Autodesk Fusion 360 part; units mm, degrees
(part 3 of 3)
sketch "M3 screw shaft (32, 16) layout" plane through (0, 0, 70.4) normal (0, 0, 1) x (1, 0, 0) in component "REFERENCE - six M3 x 10 button screws and washers"
  circle A0 centre (32, 16) radius 1.5
extrude "M3 screw shaft (32, 16)" add sketch "M3 screw shaft (32, 16) layout" along normal blind 10 bodies 31 in component "REFERENCE - six M3 x 10 button screws and washers"
ref_plane "WorkPlane6" through (0, 0, 79.9) normal (0, 0, 1) x (1, 0, 0) in component "REFERENCE - six M3 x 10 button screws and washers"
sketch "M3 washer OD (32, 16) layout" plane through (0, 0, 79.9) normal (0, 0, 1) x (1, 0, 0) in component "REFERENCE - six M3 x 10 button screws and washers"
  circle A0 centre (32, 16) radius 3.5
extrude "M3 washer OD (32, 16)" add sketch "M3 washer OD (32, 16) layout" along normal blind 0.5 bodies 31 in component "REFERENCE - six M3 x 10 button screws and washers"
ref_plane "WorkPlane3" through (0, 0, 71.1) normal (0, 0, 1) x (1, 0, 0) in component "REFERENCE - six M3 DIN 934 nuts"
sketch "M3 nut (32, 16) outline" plane through (0, 0, 71.1) normal (0, 0, 1) x (1, 0, 0) in component "REFERENCE - six M3 DIN 934 nuts"
  line L0 (35.1754, 16) -> (33.5877, 18.75)
  line L1 (33.5877, 18.75) -> (30.4123, 18.75)
  line L2 (30.4123, 18.75) -> (28.8246, 16)
  line L3 (28.8246, 16) -> (30.4123, 13.25)
  line L4 (30.4123, 13.25) -> (33.5877, 13.25)
  line L5 (33.5877, 13.25) -> (35.1754, 16)
extrude "M3 nut (32, 16)" add sketch "M3 nut (32, 16) outline" along normal blind 2.4 separate body makes body 32 in component "REFERENCE - six M3 DIN 934 nuts"
ref_plane "WorkPlane4" through (0, 0, 71) normal (0, 0, 1) x (1, 0, 0) in component "REFERENCE - six M3 DIN 934 nuts"
sketch "M3 thread clearance envelope (32, 16) layout" plane through (0, 0, 71) normal (0, 0, 1) x (1, 0, 0) in component "REFERENCE - six M3 DIN 934 nuts"
  circle A0 centre (32, 16) radius 1.6
extrude "M3 thread clearance envelope (32, 16)" cut sketch "M3 thread clearance envelope (32, 16) layout" along normal blind 2.6 bodies 30 32 in component "REFERENCE - six M3 DIN 934 nuts"
ref_plane "WorkPlane7" through (0, 0, 80.4) normal (0, 0, 1) x (1, 0, 0) in component "REFERENCE - six M3 x 10 button screws and washers"
sketch "M3 button head envelope (182, 16) layout" plane through (0, 0, 80.4) normal (0, 0, 1) x (1, 0, 0) in component "REFERENCE - six M3 x 10 button screws and washers"
  circle A0 centre (182, 16) radius 2.85
extrude "M3 button head envelope (182, 16)" add sketch "M3 button head envelope (182, 16) layout" along normal blind 1.65 separate body makes body 33 in component "REFERENCE - six M3 x 10 button screws and washers"
ref_plane "WorkPlane8" through (0, 0, 70.4) normal (0, 0, 1) x (1, 0, 0) in component "REFERENCE - six M3 x 10 button screws and washers"
sketch "M3 screw shaft (182, 16) layout" plane through (0, 0, 70.4) normal (0, 0, 1) x (1, 0, 0) in component "REFERENCE - six M3 x 10 button screws and washers"
  circle A0 centre (182, 16) radius 1.5
extrude "M3 screw shaft (182, 16)" add sketch "M3 screw shaft (182, 16) layout" along normal blind 10 bodies 33 in component "REFERENCE - six M3 x 10 button screws and washers"
ref_plane "WorkPlane9" through (0, 0, 79.9) normal (0, 0, 1) x (1, 0, 0) in component "REFERENCE - six M3 x 10 button screws and washers"
sketch "M3 washer OD (182, 16) layout" plane through (0, 0, 79.9) normal (0, 0, 1) x (1, 0, 0) in component "REFERENCE - six M3 x 10 button screws and washers"
  circle A0 centre (182, 16) radius 3.5
extrude "M3 washer OD (182, 16)" add sketch "M3 washer OD (182, 16) layout" along normal blind 0.5 bodies 33 in component "REFERENCE - six M3 x 10 button screws and washers"
ref_plane "WorkPlane5" through (0, 0, 71.1) normal (0, 0, 1) x (1, 0, 0) in component "REFERENCE - six M3 DIN 934 nuts"
sketch "M3 nut (182, 16) outline" plane through (0, 0, 71.1) normal (0, 0, 1) x (1, 0, 0) in component "REFERENCE - six M3 DIN 934 nuts"
  line L0 (185.1754, 16) -> (183.5877, 18.75)
  line L1 (183.5877, 18.75) -> (180.4123, 18.75)
  line L2 (180.4123, 18.75) -> (178.8246, 16)
  line L3 (178.8246, 16) -> (180.4123, 13.25)
  line L4 (180.4123, 13.25) -> (183.5877, 13.25)
  line L5 (183.5877, 13.25) -> (185.1754, 16)
extrude "M3 nut (182, 16)" add sketch "M3 nut (182, 16) outline" along normal blind 2.4 separate body makes body 34 in component "REFERENCE - six M3 DIN 934 nuts"
ref_plane "WorkPlane6" through (0, 0, 71) normal (0, 0, 1) x (1, 0, 0) in component "REFERENCE - six M3 DIN 934 nuts"
sketch "M3 thread clearance envelope (182, 16) layout" plane through (0, 0, 71) normal (0, 0, 1) x (1, 0, 0) in component "REFERENCE - six M3 DIN 934 nuts"
  circle A0 centre (182, 16) radius 1.6
extrude "M3 thread clearance envelope (182, 16)" cut sketch "M3 thread clearance envelope (182, 16) layout" along normal blind 2.6 bodies 30 32 34 in component "REFERENCE - six M3 DIN 934 nuts"
ref_plane "WorkPlane10" through (0, 0, 80.4) normal (0, 0, 1) x (1, 0, 0) in component "REFERENCE - six M3 x 10 button screws and washers"
sketch "M3 button head envelope (196, 16) layout" plane through (0, 0, 80.4) normal (0, 0, 1) x (1, 0, 0) in component "REFERENCE - six M3 x 10 button screws and washers"
  circle A0 centre (196, 16) radius 2.85
extrude "M3 button head envelope (196, 16)" add sketch "M3 button head envelope (196, 16) layout" along normal blind 1.65 separate body makes body 35 in component "REFERENCE - six M3 x 10 button screws and washers"
ref_plane "WorkPlane11" through (0, 0, 70.4) normal (0, 0, 1) x (1, 0, 0) in component "REFERENCE - six M3 x 10 button screws and washers"
sketch "M3 screw shaft (196, 16) layout" plane through (0, 0, 70.4) normal (0, 0, 1) x (1, 0, 0) in component "REFERENCE - six M3 x 10 button screws and washers"
  circle A0 centre (196, 16) radius 1.5
extrude "M3 screw shaft (196, 16)" add sketch "M3 screw shaft (196, 16) layout" along normal blind 10 bodies 35 in component "REFERENCE - six M3 x 10 button screws and washers"
ref_plane "WorkPlane12" through (0, 0, 79.9) normal (0, 0, 1) x (1, 0, 0) in component "REFERENCE - six M3 x 10 button screws and washers"
sketch "M3 washer OD (196, 16) layout" plane through (0, 0, 79.9) normal (0, 0, 1) x (1, 0, 0) in component "REFERENCE - six M3 x 10 button screws and washers"
  circle A0 centre (196, 16) radius 3.5
extrude "M3 washer OD (196, 16)" add sketch "M3 washer OD (196, 16) layout" along normal blind 0.5 bodies 35 in component "REFERENCE - six M3 x 10 button screws and washers"
ref_plane "WorkPlane7" through (0, 0, 71.1) normal (0, 0, 1) x (1, 0, 0) in component "REFERENCE - six M3 DIN 934 nuts"
sketch "M3 nut (196, 16) outline" plane through (0, 0, 71.1) normal (0, 0, 1) x (1, 0, 0) in component "REFERENCE - six M3 DIN 934 nuts"
  line L0 (199.1754, 16) -> (197.5877, 18.75)
  line L1 (197.5877, 18.75) -> (194.4123, 18.75)
  line L2 (194.4123, 18.75) -> (192.8246, 16)
  line L3 (192.8246, 16) -> (194.4123, 13.25)
  line L4 (194.4123, 13.25) -> (197.5877, 13.25)
  line L5 (197.5877, 13.25) -> (199.1754, 16)
extrude "M3 nut (196, 16)" add sketch "M3 nut (196, 16) outline" along normal blind 2.4 separate body makes body 36 in component "REFERENCE - six M3 DIN 934 nuts"
ref_plane "WorkPlane8" through (0, 0, 71) normal (0, 0, 1) x (1, 0, 0) in component "REFERENCE - six M3 DIN 934 nuts"
sketch "M3 thread clearance envelope (196, 16) layout" plane through (0, 0, 71) normal (0, 0, 1) x (1, 0, 0) in component "REFERENCE - six M3 DIN 934 nuts"
  circle A0 centre (196, 16) radius 1.6
extrude "M3 thread clearance envelope (196, 16)" cut sketch "M3 thread clearance envelope (196, 16) layout" along normal blind 2.6 bodies 30 32 34 36 in component "REFERENCE - six M3 DIN 934 nuts"
ref_plane "WorkPlane13" through (0, 0, 80.4) normal (0, 0, 1) x (1, 0, 0) in component "REFERENCE - six M3 x 10 button screws and washers"
sketch "M3 button head envelope (92, -2.5) layout" plane through (0, 0, 80.4) normal (0, 0, 1) x (1, 0, 0) in component "REFERENCE - six M3 x 10 button screws and washers"
  circle A0 centre (92, -2.5) radius 2.85
extrude "M3 button head envelope (92, -2.5)" add sketch "M3 button head envelope (92, -2.5) layout" along normal blind 1.65 separate body makes body 37 in component "REFERENCE - six M3 x 10 button screws and washers"
ref_plane "WorkPlane14" through (0, 0, 70.4) normal (0, 0, 1) x (1, 0, 0) in component "REFERENCE - six M3 x 10 button screws and washers"
sketch "M3 screw shaft (92, -2.5) layout" plane through (0, 0, 70.4) normal (0, 0, 1) x (1, 0, 0) in component "REFERENCE - six M3 x 10 button screws and washers"
  circle A0 centre (92, -2.5) radius 1.5
extrude "M3 screw shaft (92, -2.5)" add sketch "M3 screw shaft (92, -2.5) layout" along normal blind 10 bodies 37 in component "REFERENCE - six M3 x 10 button screws and washers"
ref_plane "WorkPlane15" through (0, 0, 79.9) normal (0, 0, 1) x (1, 0, 0) in component "REFERENCE - six M3 x 10 button screws and washers"
sketch "M3 washer OD (92, -2.5) layout" plane through (0, 0, 79.9) normal (0, 0, 1) x (1, 0, 0) in component "REFERENCE - six M3 x 10 button screws and washers"
  circle A0 centre (92, -2.5) radius 3.5
extrude "M3 washer OD (92, -2.5)" add sketch "M3 washer OD (92, -2.5) layout" along normal blind 0.5 bodies 37 in component "REFERENCE - six M3 x 10 button screws and washers"
ref_plane "WorkPlane9" through (0, 0, 71.1) normal (0, 0, 1) x (1, 0, 0) in component "REFERENCE - six M3 DIN 934 nuts"
sketch "M3 nut (92, -2.5) outline" plane through (0, 0, 71.1) normal (0, 0, 1) x (1, 0, 0) in component "REFERENCE - six M3 DIN 934 nuts"
  line L0 (95.1754, -2.5) -> (93.5877, 0.25)
  line L1 (93.5877, 0.25) -> (90.4123, 0.25)
  line L2 (90.4123, 0.25) -> (88.8246, -2.5)
  line L3 (88.8246, -2.5) -> (90.4123, -5.25)
  line L4 (90.4123, -5.25) -> (93.5877, -5.25)
  line L5 (93.5877, -5.25) -> (95.1754, -2.5)
extrude "M3 nut (92, -2.5)" add sketch "M3 nut (92, -2.5) outline" along normal blind 2.4 separate body makes body 38 in component "REFERENCE - six M3 DIN 934 nuts"
ref_plane "WorkPlane10" through (0, 0, 71) normal (0, 0, 1) x (1, 0, 0) in component "REFERENCE - six M3 DIN 934 nuts"
sketch "M3 thread clearance envelope (92, -2.5) layout" plane through (0, 0, 71) normal (0, 0, 1) x (1, 0, 0) in component "REFERENCE - six M3 DIN 934 nuts"
  circle A0 centre (92, -2.5) radius 1.6
extrude "M3 thread clearance envelope (92, -2.5)" cut sketch "M3 thread clearance envelope (92, -2.5) layout" along normal blind 2.6 bodies 30 32 34 36 38 in component "REFERENCE - six M3 DIN 934 nuts"
ref_plane "WorkPlane16" through (0, 0, 80.4) normal (0, 0, 1) x (1, 0, 0) in component "REFERENCE - six M3 x 10 button screws and washers"
sketch "M3 button head envelope (122, -2.5) layout" plane through (0, 0, 80.4) normal (0, 0, 1) x (1, 0, 0) in component "REFERENCE - six M3 x 10 button screws and washers"
  circle A0 centre (122, -2.5) radius 2.85
extrude "M3 button head envelope (122, -2.5)" add sketch "M3 button head envelope (122, -2.5) layout" along normal blind 1.65 separate body makes body 39 in component "REFERENCE - six M3 x 10 button screws and washers"
ref_plane "WorkPlane17" through (0, 0, 70.4) normal (0, 0, 1) x (1, 0, 0) in component "REFERENCE - six M3 x 10 button screws and washers"
sketch "M3 screw shaft (122, -2.5) layout" plane through (0, 0, 70.4) normal (0, 0, 1) x (1, 0, 0) in component "REFERENCE - six M3 x 10 button screws and washers"
  circle A0 centre (122, -2.5) radius 1.5
extrude "M3 screw shaft (122, -2.5)" add sketch "M3 screw shaft (122, -2.5) layout" along normal blind 10 bodies 39 in component "REFERENCE - six M3 x 10 button screws and washers"
ref_plane "WorkPlane18" through (0, 0, 79.9) normal (0, 0, 1) x (1, 0, 0) in component "REFERENCE - six M3 x 10 button screws and washers"
sketch "M3 washer OD (122, -2.5) layout" plane through (0, 0, 79.9) normal (0, 0, 1) x (1, 0, 0) in component "REFERENCE - six M3 x 10 button screws and washers"
  circle A0 centre (122, -2.5) radius 3.5
extrude "M3 washer OD (122, -2.5)" add sketch "M3 washer OD (122, -2.5) layout" along normal blind 0.5 bodies 39 in component "REFERENCE - six M3 x 10 button screws and washers"
ref_plane "WorkPlane11" through (0, 0, 71.1) normal (0, 0, 1) x (1, 0, 0) in component "REFERENCE - six M3 DIN 934 nuts"
sketch "M3 nut (122, -2.5) outline" plane through (0, 0, 71.1) normal (0, 0, 1) x (1, 0, 0) in component "REFERENCE - six M3 DIN 934 nuts"
  line L0 (125.1754, -2.5) -> (123.5877, 0.25)
  line L1 (123.5877, 0.25) -> (120.4123, 0.25)
  line L2 (120.4123, 0.25) -> (118.8246, -2.5)
  line L3 (118.8246, -2.5) -> (120.4123, -5.25)
  line L4 (120.4123, -5.25) -> (123.5877, -5.25)
  line L5 (123.5877, -5.25) -> (125.1754, -2.5)
extrude "M3 nut (122, -2.5)" add sketch "M3 nut (122, -2.5) outline" along normal blind 2.4 separate body makes body 40 in component "REFERENCE - six M3 DIN 934 nuts"
ref_plane "WorkPlane12" through (0, 0, 71) normal (0, 0, 1) x (1, 0, 0) in component "REFERENCE - six M3 DIN 934 nuts"
sketch "M3 thread clearance envelope (122, -2.5) layout" plane through (0, 0, 71) normal (0, 0, 1) x (1, 0, 0) in component "REFERENCE - six M3 DIN 934 nuts"
  circle A0 centre (122, -2.5) radius 1.6
extrude "M3 thread clearance envelope (122, -2.5)" cut sketch "M3 thread clearance envelope (122, -2.5) layout" along normal blind 2.6 bodies 30 32 34 36 38 40 in component "REFERENCE - six M3 DIN 934 nuts"
ref_plane "WorkPlane1" through (99, 0, 0) normal (1, 0, 0) x (0, 1, 0) in component "REFERENCE - v11 ribbon 16 x 0.35 mm assumed"
sketch "Illustrative ribbon clearance outline" plane through (99, 0, 0) normal (1, 0, 0) x (0, 0, -1) in component "REFERENCE - v11 ribbon 16 x 0.35 mm assumed"
  line L0 (13, -17.675) -> (8.9063, -17.675)
  line L1 (8.9063, -17.675) -> (6.825, -14.553)
  line L2 (6.825, -14.553) -> (6.825, -13.0967)
  line L3 (6.825, -13.0967) -> (3.4496, -10.975)
  line L4 (3.4496, -10.975) -> (-81.5, -10.975)
  line L5 (-81.5, -10.975) -> (-81.5, -10.625)
  line L6 (-81.5, -10.625) -> (3.5504, -10.625)
  line L7 (3.5504, -10.625) -> (7.175, -12.9033)
  line L8 (7.175, -12.9033) -> (7.175, -14.447)
  line L9 (7.175, -14.447) -> (9.0937, -17.325)
  line L10 (9.0937, -17.325) -> (13, -17.325)
  line L11 (13, -17.325) -> (13, -17.675)
extrude "Illustrative ribbon clearance" add sketch "Illustrative ribbon clearance outline" along normal blind 16 separate body makes body 41 in component "REFERENCE - v11 ribbon 16 x 0.35 mm assumed"
ref_plane "WorkPlane51" through (0, 0, 164.5) normal (0, 0, 1) x (1, 0, 0) in component "01 Electronics case - PRINT 1"
sketch "Close obsolete roof vent fragments 96 outline" plane through (0, 0, 164.5) normal (0, 0, 1) x (1, 0, 0) in component "01 Electronics case - PRINT 1"
  line L0 (96, -8) -> (99, -8)
  line L1 (99, -8) -> (99, 16)
  line L2 (99, 16) -> (96, 16)
  line L3 (96, 16) -> (96, -8)
extrude "Close obsolete roof vent fragments 96" add sketch "Close obsolete roof vent fragments 96 outline" along normal blind 2.5 bodies 13 in component "01 Electronics case - PRINT 1"
ref_plane "WorkPlane52" through (0, 0, 164.5) normal (0, 0, 1) x (1, 0, 0) in component "01 Electronics case - PRINT 1"
sketch "Close obsolete roof vent fragments 108 outline" plane through (0, 0, 164.5) normal (0, 0, 1) x (1, 0, 0) in component "01 Electronics case - PRINT 1"
  line L0 (108, -8) -> (111, -8)
  line L1 (111, -8) -> (111, 16)
  line L2 (111, 16) -> (108, 16)
  line L3 (108, 16) -> (108, -8)
extrude "Close obsolete roof vent fragments 108" add sketch "Close obsolete roof vent fragments 108 outline" along normal blind 2.5 bodies 13 in component "01 Electronics case - PRINT 1"
ref_plane "WorkPlane53" through (0, 0, 69) normal (0, 0, 1) x (1, 0, 0) in component "01 Electronics case - PRINT 1"
sketch "Close obstructed strap slot -10.8 outline" plane through (0, 0, 69) normal (0, 0, 1) x (1, 0, 0) in component "01 Electronics case - PRINT 1"
  line L0 (80, -10.8) -> (92, -10.8)
  line L1 (92, -10.8) -> (92, -8.6)
  line L2 (92, -8.6) -> (80, -8.6)
  line L3 (80, -8.6) -> (80, -10.8)
extrude "Close obstructed strap slot -10.8" add sketch "Close obstructed strap slot -10.8 outline" along normal blind 2.4 bodies 13 in component "01 Electronics case - PRINT 1"
ref_plane "WorkPlane54" through (0, 0, 69) normal (0, 0, 1) x (1, 0, 0) in component "01 Electronics case - PRINT 1"
sketch "Close obstructed strap slot 18.6 outline" plane through (0, 0, 69) normal (0, 0, 1) x (1, 0, 0) in component "01 Electronics case - PRINT 1"
  line L0 (80, 18.6) -> (92, 18.6)
  line L1 (92, 18.6) -> (92, 20.8)
  line L2 (92, 20.8) -> (80, 20.8)
  line L3 (80, 20.8) -> (80, 18.6)
extrude "Close obstructed strap slot 18.6" add sketch "Close obstructed strap slot 18.6 outline" along normal blind 2.4 bodies 13 in component "01 Electronics case - PRINT 1"
ref_plane "WorkPlane55" through (0, 0, 71.4) normal (0, 0, 1) x (1, 0, 0) in component "01 Electronics case - PRINT 1"
sketch "Restore rear wall at old strap slot outline" plane through (0, 0, 71.4) normal (0, 0, 1) x (1, 0, 0) in component "01 Electronics case - PRINT 1"
  line L0 (80, 20) -> (92, 20)
  line L1 (92, 20) -> (92, 20.8)
  line L2 (92, 20.8) -> (80, 20.8)
  line L3 (80, 20.8) -> (80, 20)
extrude "Restore rear wall at old strap slot" add sketch "Restore rear wall at old strap slot outline" along normal blind 0.1 bodies 13 in component "01 Electronics case - PRINT 1"
ref_plane "WorkPlane56" through (0, 0, 68.9) normal (0, 0, 1) x (1, 0, 0) in component "01 Electronics case - PRINT 1"
sketch "Relocated full-width battery strap slot -10.8 outline" plane through (0, 0, 68.9) normal (0, 0, 1) x (1, 0, 0) in component "01 Electronics case - PRINT 1"
  line L0 (72, -10.8) -> (84, -10.8)
  line L1 (84, -10.8) -> (84, -8.6)
  line L2 (84, -8.6) -> (72, -8.6)
  line L3 (72, -8.6) -> (72, -10.8)
extrude "Relocated full-width battery strap slot -10.8" cut sketch "Relocated full-width battery strap slot -10.8 outline" along normal blind 2.6 bodies 13 in component "01 Electronics case - PRINT 1"
ref_plane "WorkPlane57" through (0, 0, 68.9) normal (0, 0, 1) x (1, 0, 0) in component "01 Electronics case - PRINT 1"
sketch "Relocated full-width battery strap slot 18.6 outline" plane through (0, 0, 68.9) normal (0, 0, 1) x (1, 0, 0) in component "01 Electronics case - PRINT 1"
  line L0 (72, 18.6) -> (84, 18.6)
  line L1 (84, 18.6) -> (84, 20.8)
  line L2 (84, 20.8) -> (72, 20.8)
  line L3 (72, 20.8) -> (72, 18.6)
extrude "Relocated full-width battery strap slot 18.6" cut sketch "Relocated full-width battery strap slot 18.6 outline" along normal blind 2.6 bodies 13 in component "01 Electronics case - PRINT 1"
ref_plane "WorkPlane58" through (0, 0, 71.3) normal (0, 0, 1) x (1, 0, 0) in component "01 Electronics case - PRINT 1"
sketch "Rear battery strap recess 38 outline" plane through (0, 0, 71.3) normal (0, 0, 1) x (1, 0, 0) in component "01 Electronics case - PRINT 1"
  line L0 (38, 20) -> (50, 20)
  line L1 (50, 20) -> (50, 20.8)
  line L2 (50, 20.8) -> (38, 20.8)
  line L3 (38, 20.8) -> (38, 20)
extrude "Rear battery strap recess 38" cut sketch "Rear battery strap recess 38 outline" along normal blind 85 bodies 13 in component "01 Electronics case - PRINT 1"
ref_plane "WorkPlane59" through (0, 0, 71.3) normal (0, 0, 1) x (1, 0, 0) in component "01 Electronics case - PRINT 1"
sketch "Rear battery strap recess 72 outline" plane through (0, 0, 71.3) normal (0, 0, 1) x (1, 0, 0) in component "01 Electronics case - PRINT 1"
  line L0 (72, 20) -> (84, 20)
  line L1 (84, 20) -> (84, 20.8)
  line L2 (84, 20.8) -> (72, 20.8)
  line L3 (72, 20.8) -> (72, 20)
extrude "Rear battery strap recess 72" cut sketch "Rear battery strap recess 72 outline" along normal blind 85 bodies 13 in component "01 Electronics case - PRINT 1"
ref_plane "WorkPlane17" through (0, 0, -10.1) normal (0, 0, 1) x (1, 0, 0) in component "04 Downward camera carrier - PRINT 1"
sketch "Guard clearance corner (86, -23.65) outline" plane through (0, 0, -10.1) normal (0, 0, 1) x (1, 0, 0) in component "04 Downward camera carrier - PRINT 1"
  line L0 (86, -23.65) -> (94, -23.65)
  line L1 (94, -23.65) -> (86, -15.65)
  line L2 (86, -15.65) -> (86, -23.65)
extrude "Guard clearance corner (86, -23.65)" cut sketch "Guard clearance corner (86, -23.65) outline" along normal blind 4.2 bodies 15 in component "04 Downward camera carrier - PRINT 1"
ref_plane "WorkPlane18" through (0, 0, -10.1) normal (0, 0, 1) x (1, 0, 0) in component "04 Downward camera carrier - PRINT 1"
sketch "Guard clearance corner (86, 18.35) outline" plane through (0, 0, -10.1) normal (0, 0, 1) x (1, 0, 0) in component "04 Downward camera carrier - PRINT 1"
  line L0 (86, 18.35) -> (94, 18.35)
  line L1 (94, 18.35) -> (86, 10.35)
  line L2 (86, 10.35) -> (86, 18.35)
extrude "Guard clearance corner (86, 18.35)" cut sketch "Guard clearance corner (86, 18.35) outline" along normal blind 4.2 bodies 15 in component "04 Downward camera carrier - PRINT 1"
ref_plane "WorkPlane19" through (0, 0, -10.1) normal (0, 0, 1) x (1, 0, 0) in component "04 Downward camera carrier - PRINT 1"
sketch "Guard clearance corner (128, -23.65) outline" plane through (0, 0, -10.1) normal (0, 0, 1) x (1, 0, 0) in component "04 Downward camera carrier - PRINT 1"
  line L0 (128, -23.65) -> (120, -23.65)
  line L1 (120, -23.65) -> (128, -15.65)
  line L2 (128, -15.65) -> (128, -23.65)
extrude "Guard clearance corner (128, -23.65)" cut sketch "Guard clearance corner (128, -23.65) outline" along normal blind 4.2 bodies 15 in component "04 Downward camera carrier - PRINT 1"
ref_plane "WorkPlane20" through (0, 0, -10.1) normal (0, 0, 1) x (1, 0, 0) in component "04 Downward camera carrier - PRINT 1"
sketch "Guard clearance corner (128, 18.35) outline" plane through (0, 0, -10.1) normal (0, 0, 1) x (1, 0, 0) in component "04 Downward camera carrier - PRINT 1"
  line L0 (128, 18.35) -> (120, 18.35)
  line L1 (120, 18.35) -> (128, 10.35)
  line L2 (128, 10.35) -> (128, 18.35)
extrude "Guard clearance corner (128, 18.35)" cut sketch "Guard clearance corner (128, 18.35) outline" along normal blind 4.2 bodies 15 in component "04 Downward camera carrier - PRINT 1"
ref_plane "WorkPlane1" through (0, 0, -29) normal (0, 0, 1) x (1, 0, 0) in component "03 Enclosed camera guard with corner bumpers - PRINT 1"
sketch "Continuous protective camera walls outline" plane through (0, 0, -29) normal (0, 0, 1) x (1, 0, 0) in component "03 Enclosed camera guard with corner bumpers - PRINT 1"
  line L0 (85.2, -26.45) -> (128.8, -26.45)
  line L1 (130.8, -24.45) -> (130.8, 19.15)
  line L2 (128.8, 21.15) -> (85.2, 21.15)
  line L3 (83.2, 19.15) -> (83.2, -24.45)
  arc A0 (128.8, -26.45) -> (130.8, -24.45) centre (128.8, -24.45) ccw
  arc A1 (130.8, 19.15) -> (128.8, 21.15) centre (128.8, 19.15) ccw
  arc A2 (85.2, 21.15) -> (83.2, 19.15) centre (85.2, 19.15) ccw
  arc A3 (83.2, -24.45) -> (85.2, -26.45) centre (85.2, -24.45) ccw
extrude "Continuous protective camera walls" add sketch "Continuous protective camera walls outline" along normal blind 23.6 separate body makes body 42 in component "03 Enclosed camera guard with corner bumpers - PRINT 1"
ref_plane "WorkPlane2" through (0, 0, -26.6) normal (0, 0, 1) x (1, 0, 0) in component "03 Enclosed camera guard with corner bumpers - PRINT 1"
sketch "Rectangular cavity tool outline" plane through (0, 0, -26.6) normal (0, 0, 1) x (1, 0, 0) in component "03 Enclosed camera guard with corner bumpers - PRINT 1"
  line L0 (85.6, -24.05) -> (128.4, -24.05)
  line L1 (128.4, -24.05) -> (128.4, 18.75)
  line L2 (128.4, 18.75) -> (85.6, 18.75)
  line L3 (85.6, 18.75) -> (85.6, -24.05)
extrude "Rectangular cavity tool" add sketch "Rectangular cavity tool outline" along normal blind 21.3 separate body makes body 43 in component "03 Enclosed camera guard with corner bumpers - PRINT 1"
ref_plane "WorkPlane3" through (0, 0, -26.6) normal (0, 0, 1) x (1, 0, 0) in component "03 Enclosed camera guard with corner bumpers - PRINT 1"
sketch "45 degree cavity section -26.6" plane through (0, 0, -26.6) normal (0, 0, 1) x (1, 0, 0) in component "03 Enclosed camera guard with corner bumpers - PRINT 1"
  circle A0 centre (107, 0) radius 11
ref_plane "WorkPlane4" through (0, 0, -5.3) normal (0, 0, 1) x (1, 0, 0) in component "03 Enclosed camera guard with corner bumpers - PRINT 1"
sketch "45 degree cavity section -5.3" plane through (0, 0, -5.3) normal (0, 0, 1) x (1, 0, 0) in component "03 Enclosed camera guard with corner bumpers - PRINT 1"
  circle A0 centre (107, 0) radius 32.3
loft "45 degree self-supporting interior tool" add profiles "45 degree cavity section -26.6", "45 degree cavity section -5.3" section 1 section 2 separate body makes body 44 in component "03 Enclosed camera guard with corner bumpers - PRINT 1"
combine "Limit cone to rectangular interior" operation intersect target body 43 tool bodies 44 in component "03 Enclosed camera guard with corner bumpers - PRINT 1"
combine "Sloped interior around camera and lens" operation cut target body 42 tool bodies 43 in component "03 Enclosed camera guard with corner bumpers - PRINT 1"
ref_plane "WorkPlane5" through (0, 0, -29.1) normal (0, 0, 1) x (1, 0, 0) in component "03 Enclosed camera guard with corner bumpers - PRINT 1"
sketch "Round lens aperture - no printed lens cap layout" plane through (0, 0, -29.1) normal (0, 0, 1) x (1, 0, 0) in component "03 Enclosed camera guard with corner bumpers - PRINT 1"
  circle A0 centre (107, 0) radius 11
extrude "Round lens aperture - no printed lens cap" cut sketch "Round lens aperture - no printed lens cap layout" along normal blind 2.6 bodies 42 in component "03 Enclosed camera guard with corner bumpers - PRINT 1"
ref_plane "WorkPlane6" through (0, 0, -35.7) normal (0, 0, 1) x (1, 0, 0) in component "03 Enclosed camera guard with corner bumpers - PRINT 1"
sketch "Flat-surface lens bumper (83.2, -26.45) outline" plane through (0, 0, -35.7) normal (0, 0, 1) x (1, 0, 0) in component "03 Enclosed camera guard with corner bumpers - PRINT 1"
  line L0 (83.2, -26.45) -> (89.2, -26.45)
  line L1 (89.2, -26.45) -> (89.2, -20.45)
  line L2 (89.2, -20.45) -> (83.2, -20.45)
  line L3 (83.2, -20.45) -> (83.2, -26.45)
extrude "Flat-surface lens bumper (83.2, -26.45)" add sketch "Flat-surface lens bumper (83.2, -26.45) outline" along normal blind 6.7 bodies 42 in component "03 Enclosed camera guard with corner bumpers - PRINT 1"
ref_plane "WorkPlane7" through (0, 0, -35.7) normal (0, 0, 1) x (1, 0, 0) in component "03 Enclosed camera guard with corner bumpers - PRINT 1"
sketch "Flat-surface lens bumper (83.2, 15.15) outline" plane through (0, 0, -35.7) normal (0, 0, 1) x (1, 0, 0) in component "03 Enclosed camera guard with corner bumpers - PRINT 1"
  line L0 (83.2, 15.15) -> (89.2, 15.15)
  line L1 (89.2, 15.15) -> (89.2, 21.15)
  line L2 (89.2, 21.15) -> (83.2, 21.15)
  line L3 (83.2, 21.15) -> (83.2, 15.15)
extrude "Flat-surface lens bumper (83.2, 15.15)" add sketch "Flat-surface lens bumper (83.2, 15.15) outline" along normal blind 6.7 bodies 42 in component "03 Enclosed camera guard with corner bumpers - PRINT 1"
ref_plane "WorkPlane8" through (0, 0, -35.7) normal (0, 0, 1) x (1, 0, 0) in component "03 Enclosed camera guard with corner bumpers - PRINT 1"
sketch "Flat-surface lens bumper (124.8, -26.45) outline" plane through (0, 0, -35.7) normal (0, 0, 1) x (1, 0, 0) in component "03 Enclosed camera guard with corner bumpers - PRINT 1"
  line L0 (124.8, -26.45) -> (130.8, -26.45)
  line L1 (130.8, -26.45) -> (130.8, -20.45)
  line L2 (130.8, -20.45) -> (124.8, -20.45)
  line L3 (124.8, -20.45) -> (124.8, -26.45)
extrude "Flat-surface lens bumper (124.8, -26.45)" add sketch "Flat-surface lens bumper (124.8, -26.45) outline" along normal blind 6.7 bodies 42 in component "03 Enclosed camera guard with corner bumpers - PRINT 1"
ref_plane "WorkPlane9" through (0, 0, -35.7) normal (0, 0, 1) x (1, 0, 0) in component "03 Enclosed camera guard with corner bumpers - PRINT 1"
sketch "Flat-surface lens bumper (124.8, 15.15) outline" plane through (0, 0, -35.7) normal (0, 0, 1) x (1, 0, 0) in component "03 Enclosed camera guard with corner bumpers - PRINT 1"
  line L0 (124.8, 15.15) -> (130.8, 15.15)
  line L1 (130.8, 15.15) -> (130.8, 21.15)
  line L2 (130.8, 21.15) -> (124.8, 21.15)
  line L3 (124.8, 21.15) -> (124.8, 15.15)
extrude "Flat-surface lens bumper (124.8, 15.15)" add sketch "Flat-surface lens bumper (124.8, 15.15) outline" along normal blind 6.7 bodies 42 in component "03 Enclosed camera guard with corner bumpers - PRINT 1"
ref_plane "WorkPlane10" through (0, -26.6, 0) normal (0, 1, 0) x (0, 0, 1) in component "03 Enclosed camera guard with corner bumpers - PRINT 1"
sketch "Small chamfered ribbon service notch outline" plane through (0, -26.6, 0) normal (0, 1, 0) x (1, 0, 0) in component "03 Enclosed camera guard with corner bumpers - PRINT 1"
  line L0 (98, 5.3) -> (116, 5.3)
  line L1 (116, 5.3) -> (116, 7.4)
  line L2 (116, 7.4) -> (110, 13.4)
  line L3 (110, 13.4) -> (104, 13.4)
  line L4 (104, 13.4) -> (98, 7.4)
  line L5 (98, 7.4) -> (98, 5.3)
extrude "Small chamfered ribbon service notch" cut sketch "Small chamfered ribbon service notch outline" along normal blind 2.8 bodies 42 in component "03 Enclosed camera guard with corner bumpers - PRINT 1"
ref_plane "WorkPlane11" through (0, 0, -25) normal (0, 0, 1) x (1, 0, 0) in component "03 Enclosed camera guard with corner bumpers - PRINT 1"
sketch "Guard clip movement clearance 83.1 outline" plane through (0, 0, -25) normal (0, 0, 1) x (1, 0, 0) in component "03 Enclosed camera guard with corner bumpers - PRINT 1"
  line L0 (83.1, -3.6) -> (87.4, -3.6)
  line L1 (87.4, -3.6) -> (87.4, 3.6)
  line L2 (87.4, 3.6) -> (83.1, 3.6)
  line L3 (83.1, 3.6) -> (83.1, -3.6)
extrude "Guard clip movement clearance 83.1" cut sketch "Guard clip movement clearance 83.1 outline" along normal blind 19.7 bodies 42 in component "03 Enclosed camera guard with corner bumpers - PRINT 1"
ref_plane "WorkPlane12" through (0, 0, -25) normal (0, 0, 1) x (1, 0, 0) in component "03 Enclosed camera guard with corner bumpers - PRINT 1"
sketch "Guard clip movement clearance 126.6 outline" plane through (0, 0, -25) normal (0, 0, 1) x (1, 0, 0) in component "03 Enclosed camera guard with corner bumpers - PRINT 1"
  line L0 (126.6, -3.6) -> (130.9, -3.6)
  line L1 (130.9, -3.6) -> (130.9, 3.6)
  line L2 (130.9, 3.6) -> (126.6, 3.6)
  line L3 (126.6, 3.6) -> (126.6, -3.6)
extrude "Guard clip movement clearance 126.6" cut sketch "Guard clip movement clearance 126.6 outline" along normal blind 19.7 bodies 42 in component "03 Enclosed camera guard with corner bumpers - PRINT 1"
ref_plane "WorkPlane13" through (0, -3, 0) normal (0, 1, 0) x (0, 0, 1) in component "03 Enclosed camera guard with corner bumpers - PRINT 1"
sketch "Left 1.6 mm snap tongue outline" plane through (0, -3, 0) normal (0, 1, 0) x (1, 0, 0) in component "03 Enclosed camera guard with corner bumpers - PRINT 1"
  line L0 (84, 25) -> (85.6, 25)
  line L1 (85.6, 25) -> (85.6, 8.5)
  line L2 (85.6, 8.5) -> (86.7, 8.5)
  line L3 (86.7, 8.5) -> (86.7, 7)
  line L4 (86.7, 7) -> (85.6, 5.4)
  line L5 (85.6, 5.4) -> (84, 5.4)
  line L6 (84, 5.4) -> (84, 25)
extrude "Left 1.6 mm snap tongue" add sketch "Left 1.6 mm snap tongue outline" along normal blind 6 bodies 42 in component "03 Enclosed camera guard with corner bumpers - PRINT 1"
ref_plane "WorkPlane14" through (0, -3, 0) normal (0, 1, 0) x (0, 0, 1) in component "03 Enclosed camera guard with corner bumpers - PRINT 1"
sketch "Right 1.6 mm snap tongue outline" plane through (0, -3, 0) normal (0, 1, 0) x (1, 0, 0) in component "03 Enclosed camera guard with corner bumpers - PRINT 1"
  line L0 (130, 25) -> (128.4, 25)
  line L1 (128.4, 25) -> (128.4, 8.5)
  line L2 (128.4, 8.5) -> (127.3, 8.5)
  line L3 (127.3, 8.5) -> (127.3, 7)
  line L4 (127.3, 7) -> (128.4, 5.4)
  line L5 (128.4, 5.4) -> (130, 5.4)
  line L6 (130, 5.4) -> (130, 25)
extrude "Right 1.6 mm snap tongue" add sketch "Right 1.6 mm snap tongue outline" along normal blind 6 bodies 42 in component "03 Enclosed camera guard with corner bumpers - PRINT 1"
ref_plane "WorkPlane1" through (39, 0, 0) normal (1, 0, 0) x (0, 1, 0) in component "REFERENCE - v12 battery strap 10 x 1.5 mm at X44"
sketch "Strap outside envelope outline" plane through (39, 0, 0) normal (1, 0, 0) x (0, 0, -1) in component "REFERENCE - v12 battery strap 10 x 1.5 mm at X44"
  line L0 (-75.75, -10.45) -> (-80.75, -10.45)
  line L1 (-80.75, -10.45) -> (-82.75, -11.95)
  line L2 (-82.75, -11.95) -> (-159.25, -11.95)
  line L3 (-159.25, -11.95) -> (-159.25, 20.65)
  line L4 (-159.25, 20.65) -> (-75.75, 20.65)
  line L5 (-75.75, 20.65) -> (-75.75, -10.45)
extrude "Strap outside envelope" add sketch "Strap outside envelope outline" along normal blind 10 separate body makes body 45 in component "REFERENCE - v12 battery strap 10 x 1.5 mm at X44"
ref_plane "WorkPlane2" through (38.9, 0, 0) normal (1, 0, 0) x (0, 1, 0) in component "REFERENCE - v12 battery strap 10 x 1.5 mm at X44"
sketch "Strap inside opening outline" plane through (38.9, 0, 0) normal (1, 0, 0) x (0, 0, -1) in component "REFERENCE - v12 battery strap 10 x 1.5 mm at X44"
  line L0 (-77.25, -8.95) -> (-81.25, -8.95)
  line L1 (-81.25, -8.95) -> (-83.25, -10.45)
  line L2 (-83.25, -10.45) -> (-157.75, -10.45)
  line L3 (-157.75, -10.45) -> (-157.75, 19.15)
  line L4 (-157.75, 19.15) -> (-77.25, 19.15)
  line L5 (-77.25, 19.15) -> (-77.25, -8.95)
extrude "Strap inside opening" cut sketch "Strap inside opening outline" along normal blind 10.2 bodies 45 in component "REFERENCE - v12 battery strap 10 x 1.5 mm at X44"
ref_plane "WorkPlane3" through (0, 0, 110) normal (0, 0, 1) x (1, 0, 0) in component "REFERENCE - v12 battery strap 10 x 1.5 mm at X44"
sketch "Front closure overlap envelope outline" plane through (0, 0, 110) normal (0, 0, 1) x (1, 0, 0) in component "REFERENCE - v12 battery strap 10 x 1.5 mm at X44"
  line L0 (39, -13.45) -> (49, -13.45)
  line L1 (49, -13.45) -> (49, -11.95)
  line L2 (49, -11.95) -> (39, -11.95)
  line L3 (39, -11.95) -> (39, -13.45)
extrude "Front closure overlap envelope" add sketch "Front closure overlap envelope outline" along normal blind 30 bodies 45 in component "REFERENCE - v12 battery strap 10 x 1.5 mm at X44"
ref_plane "WorkPlane1" through (73, 0, 0) normal (1, 0, 0) x (0, 1, 0) in component "REFERENCE - v12 battery strap 10 x 1.5 mm at X78"
sketch "Strap outside envelope outline (2)" plane through (73, 0, 0) normal (1, 0, 0) x (0, 0, -1) in component "REFERENCE - v12 battery strap 10 x 1.5 mm at X78"
  line L0 (-75.75, -10.45) -> (-80.75, -10.45)
  line L1 (-80.75, -10.45) -> (-82.75, -11.95)
  line L2 (-82.75, -11.95) -> (-159.25, -11.95)
  line L3 (-159.25, -11.95) -> (-159.25, 20.65)
  line L4 (-159.25, 20.65) -> (-75.75, 20.65)
  line L5 (-75.75, 20.65) -> (-75.75, -10.45)
extrude "Strap outside envelope'" add sketch "Strap outside envelope outline (2)" along normal blind 10 separate body makes body 46 in component "REFERENCE - v12 battery strap 10 x 1.5 mm at X78"
ref_plane "WorkPlane2" through (72.9, 0, 0) normal (1, 0, 0) x (0, 1, 0) in component "REFERENCE - v12 battery strap 10 x 1.5 mm at X78"
sketch "Strap inside opening outline (2)" plane through (72.9, 0, 0) normal (1, 0, 0) x (0, 0, -1) in component "REFERENCE - v12 battery strap 10 x 1.5 mm at X78"
  line L0 (-77.25, -8.95) -> (-81.25, -8.95)
  line L1 (-81.25, -8.95) -> (-83.25, -10.45)
  line L2 (-83.25, -10.45) -> (-157.75, -10.45)
  line L3 (-157.75, -10.45) -> (-157.75, 19.15)
  line L4 (-157.75, 19.15) -> (-77.25, 19.15)
  line L5 (-77.25, 19.15) -> (-77.25, -8.95)
extrude "Strap inside opening'" cut sketch "Strap inside opening outline (2)" along normal blind 10.2 bodies 46 in component "REFERENCE - v12 battery strap 10 x 1.5 mm at X78"
ref_plane "WorkPlane3" through (0, 0, 110) normal (0, 0, 1) x (1, 0, 0) in component "REFERENCE - v12 battery strap 10 x 1.5 mm at X78"
sketch "Front closure overlap envelope outline (2)" plane through (0, 0, 110) normal (0, 0, 1) x (1, 0, 0) in component "REFERENCE - v12 battery strap 10 x 1.5 mm at X78"
  line L0 (73, -13.45) -> (83, -13.45)
  line L1 (83, -13.45) -> (83, -11.95)
  line L2 (83, -11.95) -> (73, -11.95)
  line L3 (73, -11.95) -> (73, -13.45)
extrude "Front closure overlap envelope'" add sketch "Front closure overlap envelope outline (2)" along normal blind 30 bodies 46 in component "REFERENCE - v12 battery strap 10 x 1.5 mm at X78"
component "REFERENCE - INIU P51L-E2 115 x 73 x 29 mm" placed x (-1, 0, 0) y (0, 0, 1) z (0, 1, 0) at (129, -14.5, 77)
component "REFERENCE - Raspberry Pi4 rotated ports" placed x (0, 0, -1) y (1, 0, 0) z (0, -1, 0) at (131, 60, 174.5)
component "REFERENCE - Waveshare RPi Camera G PCB and lens" placed x (-1, 0, 0) y (0, 1, 0) z (0, 0, -1) at (126, -21.65, -8)
component "REFERENCE - upward-stepped frame - back wall assumed" placed x (1, 0, 0) y (0, 1, 0) z (0, 0, 1) at (0, 0, 0)
component "01 Electronics case - PRINT 1" placed x (1, 0, 0) y (0, 1, 0) z (0, 0, 1) at (0, 0, 8.5)
component "02 Flat front and ribbon cover - PRINT 1" placed x (1, 0, 0) y (0, 1, 0) z (0, 0, 1) at (0, 0, 8.5)
component "04 Downward camera carrier - PRINT 1" placed x (1, 0, 0) y (0, 1, 0) z (0, 0, 1) at (0, 0, 0)
component "05 Adjustable C clamp - PRINT 2" placed x (1, 0, 0) y (0, 1, 0) z (0, 0, 1) at (25, 0, 0)
component "06 Padded pressure shoe - PRINT 2" placed x (1, 0, 0) y (0, 1, 0) z (0, 0, 1) at (25, 0, 0)
component "07 M5 hex bolt hand knob - PRINT 2" placed x (1, 0, 0) y (0, 1, 0) z (0, 0, 1) at (25, 0, 0)
component "05 Adjustable C clamp - PRINT 2" placed x (1, 0, 0) y (0, 1, 0) z (0, 0, 1) at (189, 0, 0)
component "06 Padded pressure shoe - PRINT 2" placed x (1, 0, 0) y (0, 1, 0) z (0, 0, 1) at (189, 0, 0)
component "07 M5 hex bolt hand knob - PRINT 2" placed x (1, 0, 0) y (0, 1, 0) z (0, 0, 1) at (189, 0, 0)
component "REFERENCE - v11 rubber contact pads" placed x (1, 0, 0) y (0, 1, 0) z (0, 0, 1) at (0, 0, 0)
component "REFERENCE - M5 x 30 DIN 933 clamp bolts" placed x (1, 0, 0) y (0, 1, 0) z (0, 0, 1) at (0, 0, 0)
component "REFERENCE - M5 DIN 934 captive nuts" placed x (1, 0, 0) y (0, 1, 0) z (0, 0, 1) at (0, 0, 0)
component "REFERENCE - six M3 x 10 button screws and washers" placed x (1, 0, 0) y (0, 1, 0) z (0, 0, 1) at (0, 0, 0)
component "REFERENCE - six M3 DIN 934 nuts" placed x (1, 0, 0) y (0, 1, 0) z (0, 0, 1) at (0, 0, 0)
component "REFERENCE - v11 ribbon 16 x 0.35 mm assumed" placed x (1, 0, 0) y (0, 1, 0) z (0, 0, 1) at (0, 0, 0)
component "03 Enclosed camera guard with corner bumpers - PRINT 1" placed x (1, 0, 0) y (0, 1, 0) z (0, 0, 1) at (0, 0, 0)
component "REFERENCE - v12 battery strap 10 x 1.5 mm at X44" placed x (1, 0, 0) y (0, 1, 0) z (0, 0, 1) at (0, 0, 0)
component "REFERENCE - v12 battery strap 10 x 1.5 mm at X78" placed x (1, 0, 0) y (0, 1, 0) z (0, 0, 1) at (0, 0, 0)
equation "wall = 2.4 mm" comment "Printed shell wall and tray thickness"
equation "battery_tray_height = 37 mm" comment "Battery chamber outside height"
equation "upper_height = 32 mm" comment "Pi chamber height above battery tray"
equation "lid_thickness = 2.4 mm" comment "Removable lid"
equation "pi_standoff_height = 5 mm" comment "Pi underside clearance"
equation "pad_recess_depth = 0.8 mm" comment "Use 3 mm rubber pads; 2.2 mm projects below case"
equation "camera_carrier_thickness = 3 mm" comment "Camera backplate"
equation "camera_standoff_height = 2.5 mm" comment "Clearance under camera PCB"
equation "camera_lens_opening = 22 mm" comment "Generous opening; check actual lens barrel before final print"
equation "camera_cap_height = 17 mm" comment "Cap height above carrier; lens must project beyond the front"
equation "snap_clearance = 0.35 mm" comment "Nominal printed locator clearance; fit-test before assembly"
equation "pi_screw_pilot = 2.1 mm" comment "Provisional PETG pilot. Fit-test with actual screws before the full print."
equation "d893 = pi_screw_pilot"
equation "d894 = pi_screw_pilot"
equation "d895 = pi_screw_pilot"
equation "d896 = pi_screw_pilot"
equation "camera_screw_pilot = 1.7 mm" comment "Provisional PETG pilot. Fit-test with actual screws before the full print."
equation "d898 = camera_screw_pilot"
equation "d899 = camera_screw_pilot"
equation "d900 = camera_screw_pilot"
equation "d901 = camera_screw_pilot"
equation "v11_clamp_web = 10 mm" comment "YZ profile web; print broad X face down; rebuild geometry through script to change layout"
equation "v11_clamp_jaw = 12 mm" comment "Lower jaw thickness; rebuild geometry through script to change layout"
equation "v11_upper_jaw = 8 mm" comment "Upper ledge thickness; rebuild geometry through script to change layout"
equation "v11_case_raise = 8.5 mm" comment "Electronics elevation above v10; rebuild geometry through script to change layout"
named bodies: "INIU envelope - check supplied cable position", "Pi PCB 85 x 56 x 1.6", "USB3", "USB2", "Ethernet", "USB-C", "HDMI0", "HDMI1", "Audio", "Camera PCB 25 x 24", "Approximate existing lens barrel - REFERENCE ONLY", "Open-front case", "Front cover", "Camera spine", "Pressure spreader", "Lower ledge pad 25", "Upper ledge pad 25", "Moving shoe rubber pad 25", "Lower ledge pad 189", "Upper ledge pad 189", "Moving shoe rubber pad 189", "Continuous protective camera walls", "Rectangular cavity tool"
